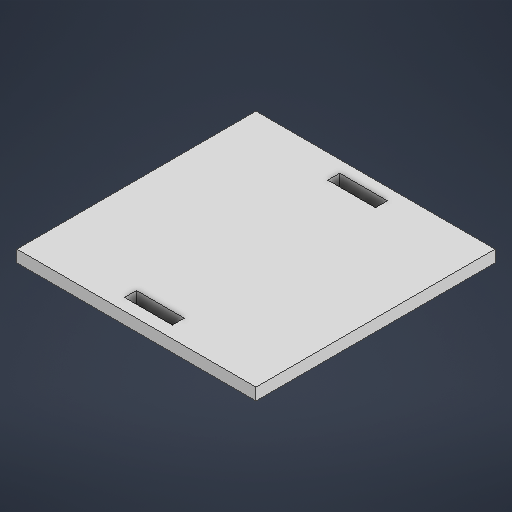
# Autodesk Inventor part: Medio
Saved by Autodesk Inventor 2025.2 (Build 292293000, 293)
## iProperties
Created: 2025-06-04
Part Number: Medio
Material: Genérico
Document SubType Name: Modeling
Designer: Niko
Density: 1 g/cm^3
Appearance: Valor por defecto
Author: Niko
Autodesk Inventor part; units mm, degrees
ref_plane "YZ Plane" through (0, 0, 0) normal (1, 0, 0) x (0, 1, 0)
ref_plane "XZ Plane" through (0, 0, 0) normal (0, 1, 0) x (-1, 0, 0)
ref_plane "XY Plane" through (0, 0, 0) normal (0, 0, 1) x (1, 0, 0)
sketch "Boceto1" plane through (0, 0, 0) normal (0, 1, 0) x (-1, 0, 0)
  line L0 (50, 50) -> (-50, 50)
  line L1 (-50, 50) -> (-50, -50)
  line L2 (-50, -50) -> (50, -50)
  line L3 (50, -50) -> (50, 50)
  line L4 (50, 30) -> (50, 50)
  line L5 (50, 50) -> (50, 45)
  line L6 (0, 45) -> (10, 45)
  line L7 (10, 45) -> (10, 40)
  line L8 (10, 40) -> (0, 40)
  line L9 (0, 45) -> (-10, 45)
  line L10 (-10, 45) -> (-10, 40)
  line L11 (-10, 40) -> (0, 40)
  line L12 (0, -45) -> (10, -45)
  line L13 (10, -45) -> (10, -40)
  line L14 (10, -40) -> (0, -40)
  line L15 (-10, -45) -> (-10, -40)
  line L16 (0, -45) -> (-10, -45)
  line L17 (-10, -40) -> (0, -40)
  constraints: 36 end point, 3 parallel, 2 horizontal, 2 perpendicular, 1 point on line
extrude "Extrusión1" add sketch "Boceto1" along normal blind 5
